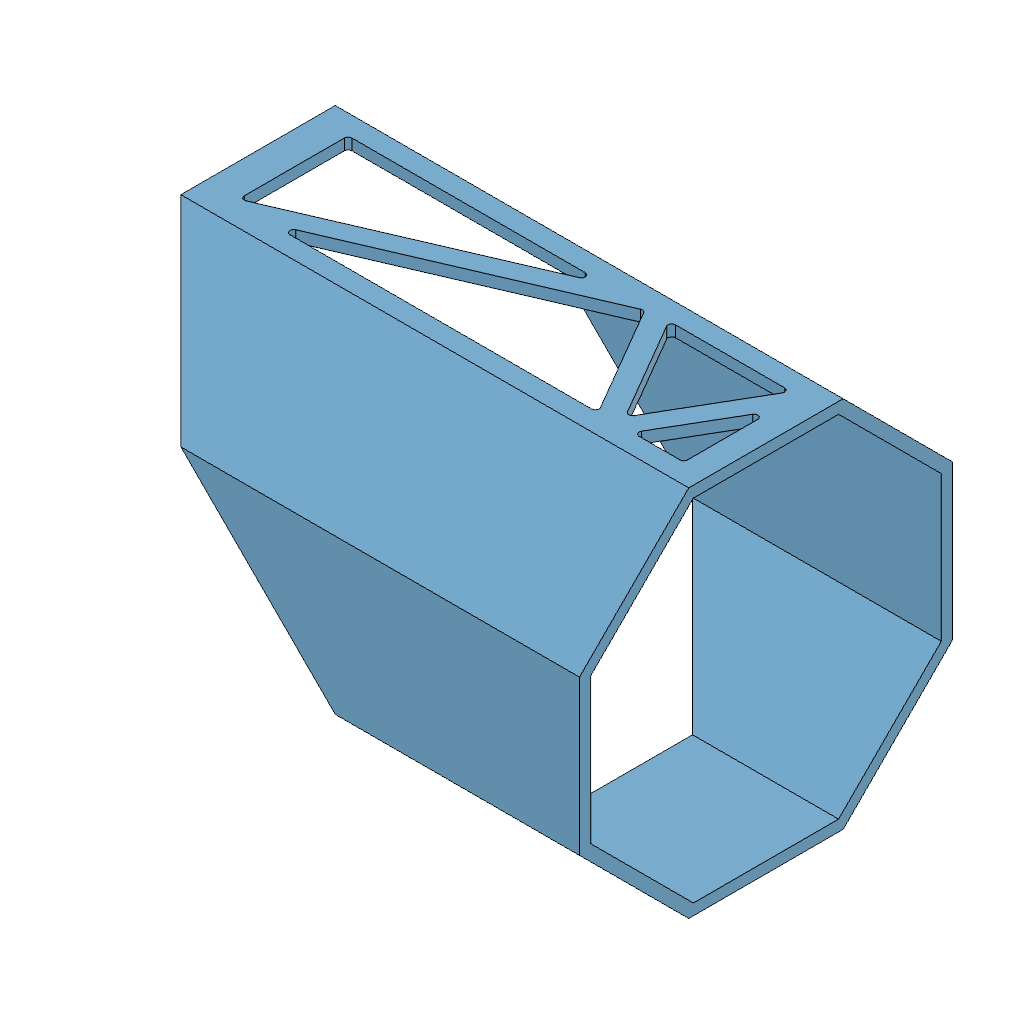
02-first-triangulated-facet (Autodesk Fusion 360 design; units mm, degrees)
part number: 2026-11-02-20-17-55-344
part number: 2026-11-02-20-17-59-218
part number: 2026-11-02-20-17-59-224
Autodesk Fusion 360 part; units mm, degrees
sketch "01 Master Octagon" plane through (0, 0, 0) normal (1, 0, 0) x (0, 0, -1)
  line L0 (75, 31.066) -> (31.066, 75)
  line L1 (31.066, 75) -> (-31.066, 75)
  line L2 (-31.066, 75) -> (-75, 31.066)
  line L3 (-75, 31.066) -> (-75, -31.066)
  line L4 (-75, -31.066) -> (-31.066, -75)
  line L5 (-31.066, -75) -> (31.066, -75)
  line L6 (31.066, -75) -> (75, -31.066)
  line L7 (75, -31.066) -> (75, 31.066)
  dimension "d59" = 150
  constraint horizontal L1
  measures "d59" vertical distance of L0.end L5.end
extrude "02 Symmetric Master Blank" add sketch "01 Master Octagon" along normal mid plane 260 makes body 1
ref_plane "WorkPlane1" through (0, 0, 12.125) normal (0.707107, 0.707107, 0) x (0, 0, 1)
split "03 Split at45 degrees" by plane through (0, 0, 12.125) normal (0.707107, 0.707107, 0) bodies 1 makes body 2 at (130, -10.3553, -25)
move_face "04 Half Gap Recess" offset -0.5 1 faces at (10.3553, -10.3553, -25) on bodies 2
move_face "04 Half Gap Recess (1)" offset -0.5 1 faces at (10.3553, -10.3553, -25) on bodies 1
copy_body "Body->Comp1" bodies 2 removing the originals makes body 3 in component "A Housing"
copy_body "Body->Comp2" bodies 1 removing the originals makes body 4 in component "B Moving Body"
shell "A Shell Open Both Ends" thickness 4.5 removed faces 2 at (-9.6482, 10.3553, -25) at (130, -10.3553, -25) on bodies 3 in component "A Housing"
shell "B Shell Open Both Ends" thickness 4.5 removed faces 2 at (-130, -10.3553, -25) at (-11.0624, 10.3553, -25) on bodies 4 in component "B Moving Body"
ref_plane "WorkPlane1" through (12.125, 0, 0) normal (0, 1, 0) x (1, 0, 0) in component "A Housing"
ref_plane "WorkPlane2" through (12.125, 75, 0) normal (0, 1, 0) x (1, 0, 0) in component "A Housing"
sketch "A Facet 0 Triangle 1" plane through (0, 75, 0) normal (0, 1, 0) x (1, 0, 0) in component "A Housing"
  line L0 (-65.1005, 27.066) -> (-65.1005, -27.066) construction
  line L1 (-65.1005, -27.066) -> (60.9665, 27.066) construction
  line L2 (60.9665, 27.066) -> (-65.1005, 27.066) construction
  line L3 (-61.1005, 23.066) -> (-61.1005, -20.9953)
  line L4 (-61.1005, -20.9953) -> (41.513, 23.066)
  line L5 (41.513, 23.066) -> (-61.1005, 23.066)
  dimension "d72" = 65.1005
  dimension "d73" = 27.066
  dimension "d74" = 65.1005
  dimension "d75" = 27.066
  dimension "d76" = 60.9665
  dimension "d77" = 27.066
  dimension "d78" = -4
  measures "d72" horizontal distance of origin L0.start
  measures "d73" vertical distance of origin L0.start
  measures "d74" horizontal distance of origin L0.end
  measures "d75" vertical distance of origin L0.end
  measures "d76" horizontal distance of origin L1.end
  measures "d77" vertical distance of origin L1.end
extrude "A Facet 0 Opening 1" cut sketch "A Facet 0 Triangle 1" against normal blind 4.7 bodies 3 in component "A Housing"
sketch "A Facet 0 Triangle 2" plane through (0, 75, 0) normal (0, 1, 0) x (1, 0, 0) in component "A Housing"
  line L0 (-65.1005, -27.066) -> (60.9665, 27.066) construction
  line L1 (60.9665, 27.066) -> (92.4832, -27.066) construction
  line L2 (92.4832, -27.066) -> (-65.1005, -27.066) construction
  line L3 (-45.647, -23.066) -> (59.2912, 21.9935)
  line L4 (59.2912, 21.9935) -> (85.5258, -23.066)
  line L5 (85.5258, -23.066) -> (-45.647, -23.066)
  dimension "d81" = 65.1005
  dimension "d82" = 27.066
  dimension "d83" = 60.9665
  dimension "d84" = 27.066
  dimension "d85" = 92.4832
  dimension "d86" = 27.066
  dimension "d87" = 4
  measures "d81" horizontal distance of origin L0.start
  measures "d82" vertical distance of origin L0.start
  measures "d83" horizontal distance of origin L0.end
  measures "d84" vertical distance of origin L0.end
  measures "d85" horizontal distance of origin L1.end
  measures "d86" vertical distance of origin L1.end
extrude "A Facet 0 Opening 2" cut sketch "A Facet 0 Triangle 2" against normal blind 4.7 bodies 3 in component "A Housing"
sketch "A Facet 0 Triangle 3" plane through (0, 75, 0) normal (0, 1, 0) x (1, 0, 0) in component "A Housing"
  line L0 (60.9665, 27.066) -> (92.4832, -27.066) construction
  line L1 (92.4832, -27.066) -> (124, 27.066) construction
  line L2 (124, 27.066) -> (60.9665, 27.066) construction
  line L3 (67.924, 23.066) -> (92.4832, -19.1161)
  line L4 (92.4832, -19.1161) -> (117.0425, 23.066)
  line L5 (117.0425, 23.066) -> (67.924, 23.066)
  dimension "d90" = 60.9665
  dimension "d91" = 27.066
  dimension "d92" = 92.4832
  dimension "d93" = 27.066
  dimension "d94" = 124
  dimension "d95" = 27.066
  dimension "d96" = -4
  measures "d90" horizontal distance of origin L0.start
  measures "d91" vertical distance of origin L0.start
  measures "d92" horizontal distance of origin L0.end
  measures "d93" vertical distance of origin L0.end
  measures "d94" horizontal distance of origin L1.end
  measures "d95" vertical distance of origin L1.end
extrude "A Facet 0 Opening 3" cut sketch "A Facet 0 Triangle 3" against normal blind 4.7 bodies 3 in component "A Housing"
sketch "A Facet 0 Triangle 4" plane through (0, 75, 0) normal (0, 1, 0) x (1, 0, 0) in component "A Housing"
  line L0 (92.4832, -27.066) -> (124, 27.066) construction
  line L1 (124, 27.066) -> (124, -27.066) construction
  line L2 (124, -27.066) -> (92.4832, -27.066) construction
  line L3 (99.4407, -23.066) -> (120, 12.2459)
  line L4 (120, 12.2459) -> (120, -23.066)
  line L5 (120, -23.066) -> (99.4407, -23.066)
  dimension "d99" = 92.4832
  dimension "d100" = 27.066
  dimension "d101" = 124
  dimension "d102" = 27.066
  dimension "d103" = 124
  dimension "d104" = 27.066
  dimension "d105" = 4
  measures "d99" horizontal distance of origin L0.start
  measures "d100" vertical distance of origin L0.start
  measures "d101" horizontal distance of origin L0.end
  measures "d102" vertical distance of origin L0.end
  measures "d103" horizontal distance of origin L1.end
  measures "d104" vertical distance of origin L1.end
extrude "A Facet 0 Opening 4" cut sketch "A Facet 0 Triangle 4" against normal blind 4.7 bodies 3 in component "A Housing"
fillet "A Facet 0 Aperture Root Radii" radius 1.5 12 edges at (120, 72.75, 23.066) (120, 72.75, -12.2459) (99.4407, 72.75, 23.066) (117.0425, 72.75, -23.066) (67.924, 72.75, -23.066) (92.4832, 72.75, 19.1161) (85.5258, 72.75, 23.066) (59.2912, 72.75, -21.9935) (-45.647, 72.75, 23.066) (41.513, 72.75, -23.066) (-61.1005, 72.75, -23.066) (-61.1005, 72.75, 20.9953) on bodies 3 in component "A Housing"
component "A Housing" placed x (1, 0, 0) y (0, 1, 0) z (0, 0, 1) at (0, 0, 0)
component "B Moving Body" placed x (1, 0, 0) y (0, 1, 0) z (0, 0, 1) at (0, 0, 0)
equation "bodyWidth = 150 mm" comment "Regular octagon across flats; corner diameter is larger."
equation "bodyLength = 260 mm" comment "Overall straight length of the shared master blank."
equation "splitAngle = 45 deg" comment "Keep this lesson angle at45 degrees."
equation "faceGap = 1 mm" comment "Gap between the two printed joint faces."
equation "wall = 4.5 mm" comment "Integrated shell and side brace radial thickness."
equation "faceHalfWidth = bodyWidth * ( sqrt(2) - 1 ) / 2" comment "Half-width of each outer planar facet."
equation "memberWidth = 8 mm" comment "Nominal brace and corner chord width in a facet."
equation "nodeHalfWidth = faceHalfWidth - memberWidth / 2" comment "Chord centerlines measured from facet center."
equation "jointNodeQ = 7 mm" comment "First truss skeleton row from the center joint plane."
equation "endRim = 10 mm" comment "Uncut axial rim at each distant end."
equation "endNodeX = bodyLength / 2 - endRim + memberWidth / 2" comment "Last skeleton row before aperture inset."
equation "apertureRadius = 1.5 mm" comment "Rounded internal corners at triangular openings."
equation "spokeWidth = 10 mm" comment "Width of each deep bearing bulkhead spoke."
equation "spokeDepth = 18 mm" comment "Bulkhead depth normal to the diagonal joint face."
equation "carrierOD = 52 mm" comment "Outside of integrated A front bearing carrier."
equation "rearCarrierClearance = 46 mm" comment "Internal carrier relief above front bearing shoulder."
equation "tubeCornerChamfer = 0.5 mm" comment "Exposed outside octagon corner bevel."
equation "tubeRimChamfer = 0.3 mm" comment "End rim and print-contact edge relief."
equation "cordStation = bodyLength / 2 - endRim / 2" comment "Load-test cord port center measured along body X."
equation "bearingOD = 22 mm" comment "608 measured outside diameter."
equation "bearingID = 8 mm" comment "608 bore."
equation "bearingWidth = 7 mm" comment "608 width."
equation "seatAllowance = 0.2 mm" comment "Trial DIAMETRAL clearance; choose with printed coupon."
equation "seatDiameter = bearingOD + seatAllowance" comment "Measured fit controls this."
equation "coreOD = 44 mm" comment "Bearing holder outer diameter."
equation "raceRelief = 19.5 mm" comment "Outer-ring shoulder opening; verify seals."
equation "frontSeatDepth = 7.1 mm" comment "0.1 mm outer-ring axial allowance."
equation "rearSeatDepth = 7.2 mm" comment "0.2 mm outer-ring axial float."
equation "shoulder = 3 mm" comment "Backing behind each bearing seat."
equation "supportSpacer = 12 mm" comment "Purchased metal M3 spacer length."
equation "supportCircle = 34 mm" comment "Three M3 support bolts."
equation "supportSpacerOD = 6 mm" comment "Purchased spacer outside diameter."
equation "capThickness = 3 mm" comment "Both printed outer-ring retaining caps."
equation "m3Clearance = 3.3 mm" comment "M3 through holes."
equation "m4Clearance = 4.3 mm" comment "M4 through holes."
equation "qFront = faceGap / 2" comment "Front bearing starts at A mating face."
equation "qFrontBack = qFront + frontSeatDepth + shoulder" comment "End of integrated A holder."
equation "qRearBase = qFrontBack + supportSpacer" comment "Start of removable rear holder."
equation "qRearBearing = qRearBase + shoulder" comment "Rear bearing inner end."
equation "qRearEnd = qRearBearing + rearSeatDepth" comment "Rear holder outer end."
equation "bearingSpacing = qRearBearing - qFront" comment "Derived support-center spacing, not a bearing rating."
equation "mountOD = 76 mm" comment "B mount and F flange outside diameter."
equation "mountCircle = 64 mm" comment "Four M4 attachment holes."
equation "mountOpening = 50.3 mm" comment "B through opening."
equation "hubFace = -23 mm" comment "Metal hub flat mounting face."
equation "adapterThickness = 6 mm" comment "F flange and metal compression sleeve length."
equation "pilotDiameter = 50 mm" comment "F shallow centering pilot."
equation "pilotInside = 34 mm" comment "Clearance around metal hub."
equation "pilotHeight = 2 mm" comment "Short pilot only."
equation "hubHoleSpacing = 16 mm" comment "Metal Sonic hub square hole spacing."
equation "sleeveOD = 8 mm" comment "M4 metal compression sleeves."
equation "sleeveAllowance = 0.2 mm" comment "Trial DIAMETRAL sleeve clearance."
equation "shaftClearance = 8.5 mm" comment "F clearance hole; not a bearing."
equation "nutAF = 7.2 mm" comment "M4 nominal 7 AF nut trial pocket."
equation "nutDepth = 4 mm" comment "Open front M4 nut pocket."
equation "rootRadius = 1 mm" comment "Hub-to-wall blend."
equation "entryChamfer = 0.4 mm" comment "Assembly lead-in."
equation "bedRelief = 0.3 mm" comment "Bed-contact edge allowance."
equation "d59 = bodyWidth"
equation "d60 = bodyLength"
equation "d62 = splitAngle"
equation "d64 = -faceGap / 2"
equation "d65 = -faceGap / 2"
equation "d66 = wall"
equation "d67 = wall"
equation "d70 = bodyWidth / 2"
equation "d72 = abs(( 1 ) * ( ( ( 1 ) * jointNodeQ * sqrt(2) - bodyWidth / 2 * cos(0 deg) + ( ( -1 ) * nodeHalfWidth ) * sin(0 deg) ) + ( 0 ) * ( ( 1 ) * endNodeX - ( ( 1 ) * jointNodeQ * sqrt(2) - bodyWidth / 2 * cos(0 deg) + ( ( -1 ) * nodeHalfWidth ) * sin(0 deg) ) ) ) + ( 0 ) * ( ( -1 ) * nodeHalfWidth ))"
equation "d73 = abs(( 0 ) * ( ( ( 1 ) * jointNodeQ * sqrt(2) - bodyWidth / 2 * cos(0 deg) + ( ( -1 ) * nodeHalfWidth ) * sin(0 deg) ) + ( 0 ) * ( ( 1 ) * endNodeX - ( ( 1 ) * jointNodeQ * sqrt(2) - bodyWidth / 2 * cos(0 deg) + ( ( -1 ) * nodeHalfWidth ) * sin(0 deg) ) ) ) + ( -1 ) * ( ( -1 ) * nodeHalfWidth ))"
equation "d74 = abs(( 1 ) * ( ( ( 1 ) * jointNodeQ * sqrt(2) - bodyWidth / 2 * cos(0 deg) + ( ( 1 ) * nodeHalfWidth ) * sin(0 deg) ) + ( 0 ) * ( ( 1 ) * endNodeX - ( ( 1 ) * jointNodeQ * sqrt(2) - bodyWidth / 2 * cos(0 deg) + ( ( 1 ) * nodeHalfWidth ) * sin(0 deg) ) ) ) + ( 0 ) * ( ( 1 ) * nodeHalfWidth ))"
equation "d75 = abs(( 0 ) * ( ( ( 1 ) * jointNodeQ * sqrt(2) - bodyWidth / 2 * cos(0 deg) + ( ( 1 ) * nodeHalfWidth ) * sin(0 deg) ) + ( 0 ) * ( ( 1 ) * endNodeX - ( ( 1 ) * jointNodeQ * sqrt(2) - bodyWidth / 2 * cos(0 deg) + ( ( 1 ) * nodeHalfWidth ) * sin(0 deg) ) ) ) + ( -1 ) * ( ( 1 ) * nodeHalfWidth ))"
equation "d76 = abs(( 1 ) * ( ( ( 1 ) * jointNodeQ * sqrt(2) - bodyWidth / 2 * cos(0 deg) + ( ( -1 ) * nodeHalfWidth ) * sin(0 deg) ) + ( 0.666666666666667 ) * ( ( 1 ) * endNodeX - ( ( 1 ) * jointNodeQ * sqrt(2) - bodyWidth / 2 * cos(0 deg) + ( ( -1 ) * nodeHalfWidth ) * sin(0 deg) ) ) ) + ( 0 ) * ( ( -1 ) * nodeHalfWidth ))"
equation "d77 = abs(( 0 ) * ( ( ( 1 ) * jointNodeQ * sqrt(2) - bodyWidth / 2 * cos(0 deg) + ( ( -1 ) * nodeHalfWidth ) * sin(0 deg) ) + ( 0.666666666666667 ) * ( ( 1 ) * endNodeX - ( ( 1 ) * jointNodeQ * sqrt(2) - bodyWidth / 2 * cos(0 deg) + ( ( -1 ) * nodeHalfWidth ) * sin(0 deg) ) ) ) + ( -1 ) * ( ( -1 ) * nodeHalfWidth ))"
equation "d78 = -memberWidth / 2"
equation "d79 = -( wall + 0.2 mm )"
equation "d81 = abs(( 1 ) * ( ( ( 1 ) * jointNodeQ * sqrt(2) - bodyWidth / 2 * cos(0 deg) + ( ( 1 ) * nodeHalfWidth ) * sin(0 deg) ) + ( 0 ) * ( ( 1 ) * endNodeX - ( ( 1 ) * jointNodeQ * sqrt(2) - bodyWidth / 2 * cos(0 deg) + ( ( 1 ) * nodeHalfWidth ) * sin(0 deg) ) ) ) + ( 0 ) * ( ( 1 ) * nodeHalfWidth ))"
equation "d82 = abs(( 0 ) * ( ( ( 1 ) * jointNodeQ * sqrt(2) - bodyWidth / 2 * cos(0 deg) + ( ( 1 ) * nodeHalfWidth ) * sin(0 deg) ) + ( 0 ) * ( ( 1 ) * endNodeX - ( ( 1 ) * jointNodeQ * sqrt(2) - bodyWidth / 2 * cos(0 deg) + ( ( 1 ) * nodeHalfWidth ) * sin(0 deg) ) ) ) + ( -1 ) * ( ( 1 ) * nodeHalfWidth ))"
equation "d83 = abs(( 1 ) * ( ( ( 1 ) * jointNodeQ * sqrt(2) - bodyWidth / 2 * cos(0 deg) + ( ( -1 ) * nodeHalfWidth ) * sin(0 deg) ) + ( 0.666666666666667 ) * ( ( 1 ) * endNodeX - ( ( 1 ) * jointNodeQ * sqrt(2) - bodyWidth / 2 * cos(0 deg) + ( ( -1 ) * nodeHalfWidth ) * sin(0 deg) ) ) ) + ( 0 ) * ( ( -1 ) * nodeHalfWidth ))"
equation "d84 = abs(( 0 ) * ( ( ( 1 ) * jointNodeQ * sqrt(2) - bodyWidth / 2 * cos(0 deg) + ( ( -1 ) * nodeHalfWidth ) * sin(0 deg) ) + ( 0.666666666666667 ) * ( ( 1 ) * endNodeX - ( ( 1 ) * jointNodeQ * sqrt(2) - bodyWidth / 2 * cos(0 deg) + ( ( -1 ) * nodeHalfWidth ) * sin(0 deg) ) ) ) + ( -1 ) * ( ( -1 ) * nodeHalfWidth ))"
equation "d85 = abs(( 1 ) * ( ( ( 1 ) * jointNodeQ * sqrt(2) - bodyWidth / 2 * cos(0 deg) + ( ( 1 ) * nodeHalfWidth ) * sin(0 deg) ) + ( 0.833333333333333 ) * ( ( 1 ) * endNodeX - ( ( 1 ) * jointNodeQ * sqrt(2) - bodyWidth / 2 * cos(0 deg) + ( ( 1 ) * nodeHalfWidth ) * sin(0 deg) ) ) ) + ( 0 ) * ( ( 1 ) * nodeHalfWidth ))"
equation "d86 = abs(( 0 ) * ( ( ( 1 ) * jointNodeQ * sqrt(2) - bodyWidth / 2 * cos(0 deg) + ( ( 1 ) * nodeHalfWidth ) * sin(0 deg) ) + ( 0.833333333333333 ) * ( ( 1 ) * endNodeX - ( ( 1 ) * jointNodeQ * sqrt(2) - bodyWidth / 2 * cos(0 deg) + ( ( 1 ) * nodeHalfWidth ) * sin(0 deg) ) ) ) + ( -1 ) * ( ( 1 ) * nodeHalfWidth ))"
equation "d87 = memberWidth / 2"
equation "d88 = -( wall + 0.2 mm )"
equation "d90 = abs(( 1 ) * ( ( ( 1 ) * jointNodeQ * sqrt(2) - bodyWidth / 2 * cos(0 deg) + ( ( -1 ) * nodeHalfWidth ) * sin(0 deg) ) + ( 0.666666666666667 ) * ( ( 1 ) * endNodeX - ( ( 1 ) * jointNodeQ * sqrt(2) - bodyWidth / 2 * cos(0 deg) + ( ( -1 ) * nodeHalfWidth ) * sin(0 deg) ) ) ) + ( 0 ) * ( ( -1 ) * nodeHalfWidth ))"
equation "d91 = abs(( 0 ) * ( ( ( 1 ) * jointNodeQ * sqrt(2) - bodyWidth / 2 * cos(0 deg) + ( ( -1 ) * nodeHalfWidth ) * sin(0 deg) ) + ( 0.666666666666667 ) * ( ( 1 ) * endNodeX - ( ( 1 ) * jointNodeQ * sqrt(2) - bodyWidth / 2 * cos(0 deg) + ( ( -1 ) * nodeHalfWidth ) * sin(0 deg) ) ) ) + ( -1 ) * ( ( -1 ) * nodeHalfWidth ))"
equation "d92 = abs(( 1 ) * ( ( ( 1 ) * jointNodeQ * sqrt(2) - bodyWidth / 2 * cos(0 deg) + ( ( 1 ) * nodeHalfWidth ) * sin(0 deg) ) + ( 0.833333333333333 ) * ( ( 1 ) * endNodeX - ( ( 1 ) * jointNodeQ * sqrt(2) - bodyWidth / 2 * cos(0 deg) + ( ( 1 ) * nodeHalfWidth ) * sin(0 deg) ) ) ) + ( 0 ) * ( ( 1 ) * nodeHalfWidth ))"
equation "d93 = abs(( 0 ) * ( ( ( 1 ) * jointNodeQ * sqrt(2) - bodyWidth / 2 * cos(0 deg) + ( ( 1 ) * nodeHalfWidth ) * sin(0 deg) ) + ( 0.833333333333333 ) * ( ( 1 ) * endNodeX - ( ( 1 ) * jointNodeQ * sqrt(2) - bodyWidth / 2 * cos(0 deg) + ( ( 1 ) * nodeHalfWidth ) * sin(0 deg) ) ) ) + ( -1 ) * ( ( 1 ) * nodeHalfWidth ))"
equation "d94 = abs(( 1 ) * ( ( ( 1 ) * jointNodeQ * sqrt(2) - bodyWidth / 2 * cos(0 deg) + ( ( -1 ) * nodeHalfWidth ) * sin(0 deg) ) + ( 1 ) * ( ( 1 ) * endNodeX - ( ( 1 ) * jointNodeQ * sqrt(2) - bodyWidth / 2 * cos(0 deg) + ( ( -1 ) * nodeHalfWidth ) * sin(0 deg) ) ) ) + ( 0 ) * ( ( -1 ) * nodeHalfWidth ))"
equation "d95 = abs(( 0 ) * ( ( ( 1 ) * jointNodeQ * sqrt(2) - bodyWidth / 2 * cos(0 deg) + ( ( -1 ) * nodeHalfWidth ) * sin(0 deg) ) + ( 1 ) * ( ( 1 ) * endNodeX - ( ( 1 ) * jointNodeQ * sqrt(2) - bodyWidth / 2 * cos(0 deg) + ( ( -1 ) * nodeHalfWidth ) * sin(0 deg) ) ) ) + ( -1 ) * ( ( -1 ) * nodeHalfWidth ))"
equation "d96 = -memberWidth / 2"
equation "d97 = -( wall + 0.2 mm )"
equation "d99 = abs(( 1 ) * ( ( ( 1 ) * jointNodeQ * sqrt(2) - bodyWidth / 2 * cos(0 deg) + ( ( 1 ) * nodeHalfWidth ) * sin(0 deg) ) + ( 0.833333333333333 ) * ( ( 1 ) * endNodeX - ( ( 1 ) * jointNodeQ * sqrt(2) - bodyWidth / 2 * cos(0 deg) + ( ( 1 ) * nodeHalfWidth ) * sin(0 deg) ) ) ) + ( 0 ) * ( ( 1 ) * nodeHalfWidth ))"
equation "d100 = abs(( 0 ) * ( ( ( 1 ) * jointNodeQ * sqrt(2) - bodyWidth / 2 * cos(0 deg) + ( ( 1 ) * nodeHalfWidth ) * sin(0 deg) ) + ( 0.833333333333333 ) * ( ( 1 ) * endNodeX - ( ( 1 ) * jointNodeQ * sqrt(2) - bodyWidth / 2 * cos(0 deg) + ( ( 1 ) * nodeHalfWidth ) * sin(0 deg) ) ) ) + ( -1 ) * ( ( 1 ) * nodeHalfWidth ))"
equation "d101 = abs(( 1 ) * ( ( ( 1 ) * jointNodeQ * sqrt(2) - bodyWidth / 2 * cos(0 deg) + ( ( -1 ) * nodeHalfWidth ) * sin(0 deg) ) + ( 1 ) * ( ( 1 ) * endNodeX - ( ( 1 ) * jointNodeQ * sqrt(2) - bodyWidth / 2 * cos(0 deg) + ( ( -1 ) * nodeHalfWidth ) * sin(0 deg) ) ) ) + ( 0 ) * ( ( -1 ) * nodeHalfWidth ))"
equation "d102 = abs(( 0 ) * ( ( ( 1 ) * jointNodeQ * sqrt(2) - bodyWidth / 2 * cos(0 deg) + ( ( -1 ) * nodeHalfWidth ) * sin(0 deg) ) + ( 1 ) * ( ( 1 ) * endNodeX - ( ( 1 ) * jointNodeQ * sqrt(2) - bodyWidth / 2 * cos(0 deg) + ( ( -1 ) * nodeHalfWidth ) * sin(0 deg) ) ) ) + ( -1 ) * ( ( -1 ) * nodeHalfWidth ))"
equation "d103 = abs(( 1 ) * ( ( ( 1 ) * jointNodeQ * sqrt(2) - bodyWidth / 2 * cos(0 deg) + ( ( 1 ) * nodeHalfWidth ) * sin(0 deg) ) + ( 1 ) * ( ( 1 ) * endNodeX - ( ( 1 ) * jointNodeQ * sqrt(2) - bodyWidth / 2 * cos(0 deg) + ( ( 1 ) * nodeHalfWidth ) * sin(0 deg) ) ) ) + ( 0 ) * ( ( 1 ) * nodeHalfWidth ))"
equation "d104 = abs(( 0 ) * ( ( ( 1 ) * jointNodeQ * sqrt(2) - bodyWidth / 2 * cos(0 deg) + ( ( 1 ) * nodeHalfWidth ) * sin(0 deg) ) + ( 1 ) * ( ( 1 ) * endNodeX - ( ( 1 ) * jointNodeQ * sqrt(2) - bodyWidth / 2 * cos(0 deg) + ( ( 1 ) * nodeHalfWidth ) * sin(0 deg) ) ) ) + ( -1 ) * ( ( 1 ) * nodeHalfWidth ))"
equation "d105 = memberWidth / 2"
equation "d106 = -( wall + 0.2 mm )"
equation "d109 = apertureRadius"
named bodies: "A Housing print", "B Moving Body print"
